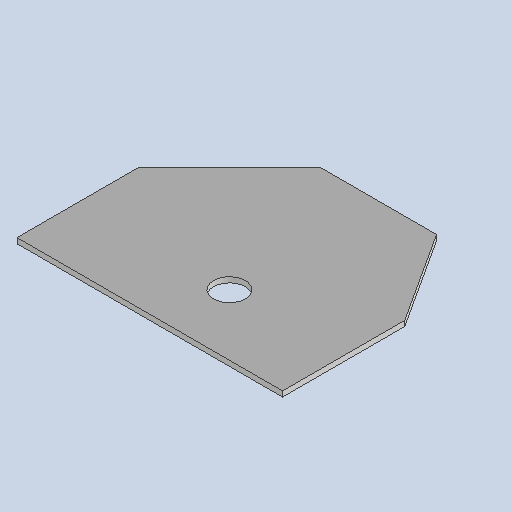
# Autodesk Inventor part: RDS-5006 Mixer Plate 500x400
Saved by Autodesk Inventor 2026.2 (Build 302298000, 298)
## iProperties
Created: 2024-04-03
Part Number: RDS-5006 Mixer Plate 500x400
Material: Generic
Document SubType Name: Modeling
Designer: admin
Density: 1 g/cm^3
Appearance: Default
Stock Number: Пластина мешалки (СДР 080)
Author: admin
Autodesk Inventor part; units mm, degrees
ref_plane "YZ Plane" through (0, 0, 0) normal (1, 0, 0) x (0, 1, 0)
ref_plane "XZ Plane" through (0, 0, 0) normal (0, 1, 0) x (-1, 0, 0)
ref_plane "XY Plane" through (0, 0, 0) normal (0, 0, 1) x (1, 0, 0)
sketch "Sketch1" plane through (0, 0, 0) normal (0, 0, 1) x (1, 0, 0)
  line L0 (-250, -200) -> (250, -200)
  line L1 (250, -200) -> (250, 200)
  line L2 (250, 200) -> (-250, 200)
  line L3 (-250, 200) -> (-250, -200)
  line L4 (-250, -200) -> (250, 200) construction
  line L5 (250, -200) -> (-250, 200) construction
  line L6 (-250, 30) -> (-80, 200)
  circle A0 centre (35, -85) radius 30
  line L7 (140, 200) -> (250, 30)
  point P0 (0, 0)
  dimension "d0" = 500
  dimension "d1" = 400
  dimension "d4" = 170
  dimension "d5" = 170
  dimension "d6" = 60
  dimension "d7" = 115
  dimension "d8" = 285
  dimension "d9" = 170
  dimension "d10" = 220
  constraints: 16 end point, 4 point on line, 2 midpoint, 2 parallel, 1 centre point, 1 horizontal, 1 perpendicular
  measures "d0" distance of L2.end L1.end
  measures "d1" distance of L1.end L0.end
  measures "d4" distance of L2.end L6.start
  measures "d5" distance of L2.end L6.end
  measures "d6" diameter of A0
  measures "d7" distance from line of A0.centre L0
  measures "d8" distance from line of A0.centre L3
  measures "d9" distance of L1.end L7.end
  measures "d10" distance of L6.end L7.start
extrude "Extrusion1" add sketch "Sketch1" along normal blind 10 contours L3 L6 L2 L7 L1 L0
equation "\"d5\" = d4"
equation "\"d9\" = d4"
body "Solid1"
